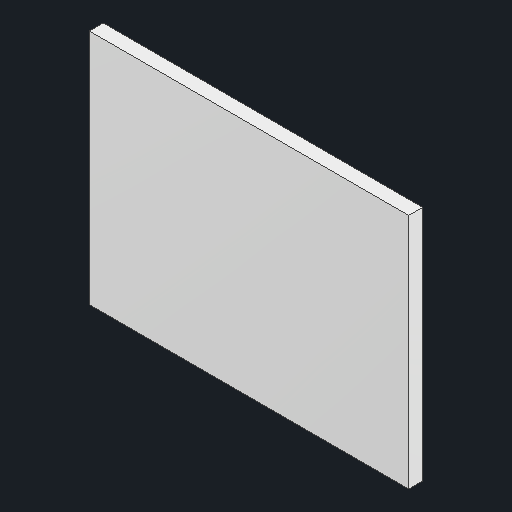
# Autodesk Inventor part: tft_1.8in_panel
Saved by Autodesk Inventor 2027.1 (Build 311270010, 270A)
## iProperties
Created: 2026-10-29
Part Number: tft_1.8in_panel
Material: Generic
Document SubType Name: Modeling
Designer: alexg
Density: 1 g/cm^3
Appearance: Smooth - White
Author: alexg
Autodesk Inventor part; units mm, degrees
ref_plane "YZ Plane" through (0, 0, 0) normal (1, 0, 0) x (0, 1, 0)
ref_plane "XZ Plane" through (0, 0, 0) normal (0, 1, 0) x (-1, 0, 0)
ref_plane "Work Plane1" through (0, 0, 25.4) normal (0, 0, 1) x (1, 0, 0)
sketch "Panel frame sketch" plane through (0, 0, 25.4) normal (0, 0, 1) x (1, 0, 0)
  line L0 (-24.97, 25.5) -> (20.86, 25.5)
  line L1 (20.86, 25.5) -> (20.86, 59.5)
  line L2 (20.86, 59.5) -> (-24.97, 59.5)
  line L3 (-24.97, 59.5) -> (-24.97, 25.5)
  constraints: 8 end point, 2 parallel, 1 horizontal, 1 perpendicular
extrude "Panel frame" add sketch "Panel frame sketch" along normal blind 2
body "Solid1"
